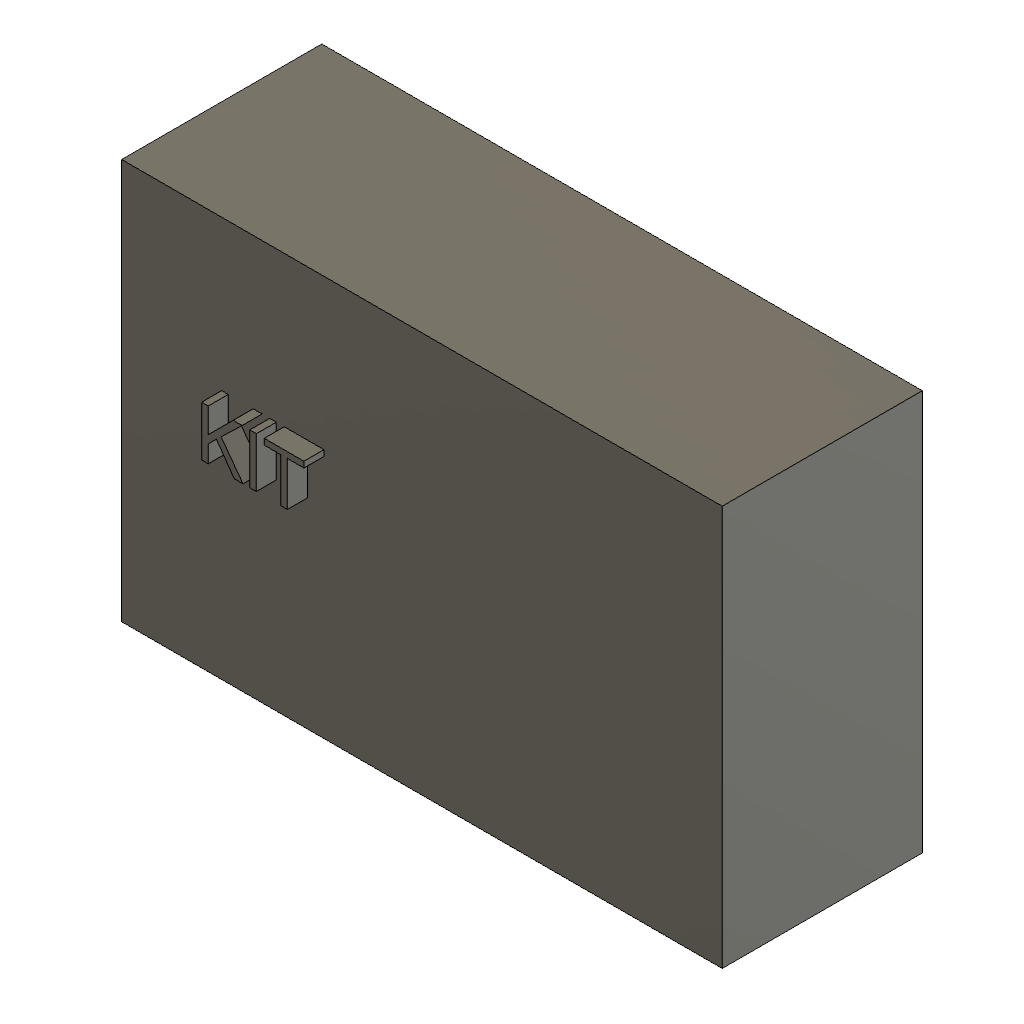
text_emboss (Autodesk Fusion 360 design; units mm, degrees)
part number: 2026-10-20-23-24-36-223
Autodesk Fusion 360 part; units mm, degrees
sketch "EmbossTextTargetSection" plane through (0, 0, 0) normal (0, 0, 1) x (1, 0, 0)
  line L0 (0, 0) -> (60, 0)
  line L1 (60, 0) -> (60, 40)
  line L2 (60, 40) -> (0, 40)
  line L3 (0, 40) -> (0, 0)
extrude "EmbossTextTargetExtrude" add sketch "EmbossTextTargetSection" along normal blind 20
ref_plane "WorkPlane1" through (0, 0, 25) normal (0, 0, 1) x (1, 0, 0)
sketch "EmbossTextInputs" plane through (0, 0, 25) normal (0, 0, 1) x (1, 0, 0)
  line L0 (10, 10) -> (30, 10) construction
  line L1 (30, 10) -> (30, 25) construction
  line L2 (30, 25) -> (10, 25) construction
  line L3 (10, 25) -> (10, 10) construction
  dimension "d5" = 5
  text T0 "KIT" font "Arial" height 5 align left top in box 20 x 15 at (10, 10) x (1, 0) y (0, 1) spacing 1 kerned
emboss "ProbeEmbossText" depth 2 profiles "EmbossTextInputs" section 1 text T0 onto face at (20, 26.6667, 20)
equation "d6 = 'KIT'"
named bodies: "EmbossTextTargetBody"
